Autodesk Fusion 360 part; units mm, degrees
(part 2 of 3)
  line L572 (36.370346, 133.075897) -> (50.340346, 133.075897)
  line L573 (36.370346, 142.565337) -> (36.370346, 137.556457)
  line L574 (50.340346, 118.508997) -> (50.340346, 123.517877)
  line L575 (35.557546, 127.017997) -> (35.557546, 123.517877)
  line L576 (151.165646, 135.961337) -> (151.165646, 139.461457)
  line L577 (36.370346, 95.958877) -> (36.370346, 94.978437)
  line L578 (35.557546, 76.908877) -> (36.370346, 76.908877)
  line L579 (50.340346, 75.928437) -> (50.340346, 76.908877)
  line L580 (40.807846, 170.435327) -> (40.807846, 172.435327)
  line L581 (50.340346, 114.028437) -> (50.340346, 115.008877)
  line L582 (75, 170.435327) -> (75, 160.233267)
  line L583 (50.340346, 137.556457) -> (50.340346, 142.565337)
  line L584 (151.165646, 139.461457) -> (150.352846, 139.461457)
  line L585 (51.153146, 123.517877) -> (51.153146, 127.017997)
  line L586 (51.153146, 118.508997) -> (50.340346, 118.508997)
  line L587 (36.370346, 123.517877) -> (36.370346, 118.508997)
  line L588 (50.340346, 89.898437) -> (36.370346, 89.898437)
  line L589 (50.340346, 85.417877) -> (51.153146, 85.417877)
  line L590 (35.557546, 95.958877) -> (36.370346, 95.958877)
  line L591 (35.557546, 134.056337) -> (36.370346, 134.056337)
  line L592 (165.973846, 183.698097) -> (174.0868, 183.698)
  line L593 (50.340346, 95.958877) -> (51.153146, 95.958877)
  line L594 (50.340346, 123.517877) -> (51.153146, 123.517877)
  line L595 (153.609126, 68.945977) -> (152.212126, 65.953857)
  line L596 (172.062226, 33.995577) -> (159.400326, 39.898537)
  line L597 (51.153146, 107.967997) -> (50.340346, 107.967997)
  line L598 (35.557546, 104.467877) -> (36.370346, 104.467877)
  line L599 (40.807846, 172.435327) -> (52.807846, 172.435327)
  line L600 (38.307846, 160.233267) -> (38.307846, 170.435327)
  circle A0 centre (216.558535, 69.898485) radius 1.5
  line L601 (36.370346, 80.408997) -> (35.557546, 80.408997)
  circle A1 centre (174.816574, 177.434124) radius 1.5
  line L602 (155.037046, 163.5842) -> (142.266246, 163.5842)
  arc A2 (221.924959, 66.584374) -> (218.538915, 75.886932) centre (215.580795, 69.542681) ccw
  line L603 (35.557546, 80.408997) -> (35.557546, 76.908877)
  line L604 (36.370346, 75.928437) -> (50.340346, 75.928437)
  line L605 (169.491746, 61.539337) -> (168.094746, 58.547217)
  line L606 (168.094746, 58.547217) -> (180.756646, 52.641717)
  circle A3 centre (106.66988, 49.713) radius 1.5
  line L607 (50.340346, 80.408997) -> (50.340346, 85.417877)
  line L608 (156.179606, 41.402217) -> (143.517706, 47.307717)
  line L609 (159.400326, 39.898537) -> (158.005866, 36.906417)
  arc A4 (181.0868, 97.809303) -> (185.12868, 91.465051) centre (188.0868, 97.809303) ccw
  line L610 (35.557546, 85.417877) -> (36.370346, 85.417877)
  circle A5 centre (26.263877, 177.434124) radius 1.5
  line L611 (50.340346, 107.967997) -> (50.340346, 108.948437)
  arc A6 (181.0868, 176.698) -> (174.0868, 183.698) centre (174.0868, 176.698) ccw
  line L612 (158.005866, 36.906417) -> (170.665226, 31.003457)
  line L613 (50.340346, 76.908877) -> (51.153146, 76.908877)
  line L614 (27, 183.698) -> (130.871308, 183.698)
  line L615 (51.153146, 88.917997) -> (50.340346, 88.917997)
  line L616 (51.153146, 76.908877) -> (51.153146, 80.408997)
  line L617 (166.268486, 63.043017) -> (153.609126, 68.945977)
  line L618 (50.340346, 88.917997) -> (50.340346, 89.898437)
  line L619 (152.212126, 65.953857) -> (164.874026, 60.050897)
  circle A7 centre (121.333346, 179.253097) radius 1.5
  line L620 (144.750746, 178.585077) -> (130.871308, 183.698)
  line L621 (181.0868, 176.698) -> (181.0868, 97.809303)
  line L622 (185.12868, 91.465051) -> (218.538915, 75.886932)
  line L623 (142.123246, 44.315597) -> (154.782606, 38.410097)
  line L624 (143.517706, 47.307717) -> (142.123246, 44.315597)
  line L625 (35.557546, 88.917997) -> (35.557546, 85.417877)
  line L626 (221.924959, 66.584374) -> (178.566521, -26.398891)
  line L627 (36.370346, 88.917997) -> (35.557546, 88.917997)
  line L628 (165.973846, 183.698097) -> (152.094146, 178.585077)
  circle A8 centre (26.263876, 53.119376) radius 1.5
  arc A9 (27, 183.698) -> (20, 176.698) centre (27, 176.698) ccw
  line L629 (52.807846, 170.435327) -> (75, 170.435327)
  line L630 (51.153146, 104.467877) -> (51.153146, 107.967997)
  line L631 (180.756646, 52.641717) -> (182.151106, 55.633837)
  line L632 (51.153146, 80.408997) -> (50.340346, 80.408997)
  line L633 (182.151106, 55.633837) -> (169.491746, 61.539337)
  line L634 (170.665226, 31.003457) -> (172.062226, 33.995577)
  line L635 (50.340346, 104.467877) -> (51.153146, 104.467877)
  line L636 (36.370346, 89.898437) -> (36.370346, 88.917997)
  line L637 (164.874026, 60.050897) -> (166.268486, 63.043017)
  line L638 (36.370346, 76.908877) -> (36.370346, 75.928437)
  line L639 (36.370346, 85.417877) -> (36.370346, 80.408997)
  line L640 (51.153146, 85.417877) -> (51.153146, 88.917997)
  line L641 (52.807846, 170.435327) -> (52.807846, 172.435327)
  line L642 (154.782606, 38.410097) -> (156.179606, 41.402217)
  line L643 (20, -23.440584) -> (20, 176.698)
  line L644 (155.037046, 174.584297) -> (155.037046, 177.084297)
  line L645 (38.307846, 170.435327) -> (40.807846, 170.435327)
  line L646 (144.750746, 178.585077) -> (145.537046, 178.585077)
  arc A10 (172.222357, -30.440584) -> (178.566521, -26.398891) centre (172.222357, -23.440584) ccw
  line L647 (40.807846, 158.233267) -> (52.807846, 158.233267)
  line L648 (142.266246, 177.084297) -> (145.537046, 177.084297)
  line L649 (145.537046, 177.084297) -> (145.537046, 178.585077)
  line L650 (38.307846, 160.233267) -> (40.807846, 160.233267)
  line L651 (151.537046, 178.585077) -> (151.537046, 177.084297)
  line L652 (142.266246, 177.084297) -> (142.266246, 173.541483)
  line L653 (158.032597, 166.625184) -> (158.033388, 174.584297)
  line L654 (52.807846, 160.233267) -> (75, 160.233267)
  circle A11 centre (26.263876, -24.176684) radius 1.5
  line L655 (155.037046, 163.5842) -> (155.037046, 166.62711)
  arc A12 (20, -23.440584) -> (27, -30.440584) centre (27, -23.440584) ccw
  line L656 (155.037046, 174.584297) -> (158.033388, 174.584297)
  line L657 (142.266246, 165.584297) -> (139.270694, 165.58237)
  line L658 (151.537046, 177.084297) -> (155.037046, 177.084297)
  line L659 (155.037046, 166.62711) -> (158.032597, 166.625184)
  circle A13 centre (172.941014, -24.568646) radius 1.5
  line L660 (172.222357, -30.440584) -> (27, -30.440584)
  line L661 (139.270694, 165.58237) -> (139.269904, 173.541483)
  line L662 (40.807846, 158.233267) -> (40.807846, 160.233267)
  line L663 (142.266246, 165.584297) -> (142.266246, 163.5842)
  line L664 (151.537046, 178.585077) -> (152.094146, 178.585077)
  line L665 (142.266246, 173.541483) -> (139.269904, 173.541483)
  line L666 (52.807846, 158.233267) -> (52.807846, 160.233267)
  line L667 (116.520046, 73.042997) -> (116.520046, 69.542877)
  line L668 (156.883186, 44.716917) -> (162.788686, 57.378817)
  line L669 (132.115646, 69.542877) -> (132.115646, 73.042997)
  line L670 (113.065646, 66.131657) -> (112.252846, 66.131657)
  line L671 (112.252846, 71.140537) -> (113.065646, 71.140537)
  line L672 (131.302846, 69.542877) -> (132.115646, 69.542877)
  line L673 (112.252846, 61.651097) -> (112.252846, 62.631537)
  line L674 (60.182846, 61.358997) -> (59.370046, 61.358997)
  line L675 (132.115646, 61.033877) -> (132.115646, 64.533997)
  line L676 (132.115646, 64.533997) -> (131.302846, 64.533997)
  line L677 (132.115646, 73.042997) -> (131.302846, 73.042997)
  line L678 (117.332846, 64.533997) -> (116.520046, 64.533997)
  line L679 (59.370046, 61.358997) -> (59.370046, 57.858877)
  line L680 (98.282846, 62.631537) -> (98.282846, 61.651097)
  line L681 (162.788686, 57.378817) -> (161.899686, 57.792837)
  line L682 (97.470046, 62.631537) -> (98.282846, 62.631537)
  line L683 (131.302846, 64.533997) -> (131.302846, 69.542877)
  line L684 (117.332846, 61.033877) -> (117.332846, 60.053437)
  line L685 (131.302846, 73.042997) -> (131.302846, 74.023437)
  line L686 (97.470046, 71.140537) -> (98.282846, 71.140537)
  line L687 (98.282846, 61.651097) -> (112.252846, 61.651097)
  line L688 (113.065646, 71.140537) -> (113.065646, 74.640657)
  line L689 (161.899686, 57.792837) -> (162.242586, 58.529437)
  line L690 (74.152846, 56.878437) -> (74.152846, 57.858877)
  line L691 (98.282846, 75.621097) -> (98.282846, 74.640657)
  line L692 (112.252846, 66.131657) -> (112.252846, 71.140537)
  line L693 (117.332846, 60.053437) -> (131.302846, 60.053437)
  line L694 (74.152846, 66.367877) -> (74.965646, 66.367877)
  line L695 (74.965646, 69.867997) -> (74.152846, 69.867997)
  line L696 (112.252846, 62.631537) -> (113.065646, 62.631537)
  line L697 (94.015646, 121.683997) -> (93.202846, 121.683997)
  line L698 (159.070126, 60.010257) -> (158.727226, 59.273657)
  line L699 (135.570046, 135.961337) -> (136.382846, 135.961337)
  line L700 (116.520046, 61.033877) -> (117.332846, 61.033877)
  line L701 (74.965646, 66.367877) -> (74.965646, 69.867997)
  line L702 (151.358686, 63.604357) -> (151.015786, 62.867757)
  line L703 (136.382846, 139.461457) -> (135.570046, 139.461457)
  line L704 (162.374666, 42.156597) -> (162.031766, 41.419997)
  line L705 (74.152846, 57.858877) -> (74.965646, 57.858877)
  line L706 (93.202846, 117.203437) -> (93.202846, 118.183877)
  line L707 (94.015646, 130.192997) -> (93.202846, 130.192997)
  line L708 (144.221286, 50.622417) -> (145.110286, 50.208397)
  line L709 (173.258566, 37.081677) -> (174.147566, 36.665117)
  line L710 (60.182846, 56.878437) -> (74.152846, 56.878437)
  line L711 (93.202846, 130.192997) -> (93.202846, 131.173437)
  line L712 (165.204226, 39.939177) -> (165.547126, 40.675777)
  line L713 (147.939846, 47.990977) -> (148.282746, 48.727577)
  line L714 (162.242586, 58.529437) -> (159.070126, 60.010257)
  line L715 (165.547126, 40.675777) -> (170.086106, 38.559957)
  line L716 (79.232846, 131.173437) -> (79.232846, 130.192997)
  line L717 (150.126786, 63.284317) -> (144.221286, 50.622417)
  line L718 (154.531146, 62.126077) -> (151.358686, 63.604357)
  line L719 (74.152846, 61.358997) -> (74.152846, 66.367877)
  line L720 (116.520046, 69.542877) -> (117.332846, 69.542877)
  line L721 (60.182846, 66.367877) -> (60.182846, 61.358997)
  line L722 (158.727226, 59.273657) -> (154.188246, 61.389477)
  line L723 (174.147566, 36.665117) -> (180.053066, 49.327017)
  line L724 (59.370046, 66.367877) -> (60.182846, 66.367877)
  line L725 (131.302846, 74.023437) -> (117.332846, 74.023437)
  line L726 (112.252846, 75.621097) -> (98.282846, 75.621097)
  line L727 (154.188246, 61.389477) -> (154.531146, 62.126077)
  line L728 (168.623066, 55.552557) -> (168.280166, 54.815957)
  line L729 (170.086106, 38.559957) -> (169.743206, 37.823357)
  line L730 (136.382846, 147.970457) -> (135.570046, 147.970457)
  line L731 (136.382846, 135.961337) -> (136.382846, 134.980897)
  line L732 (150.352846, 134.980897) -> (150.352846, 135.961337)
  line L733 (98.282846, 74.640657) -> (97.470046, 74.640657)
  line L734 (93.202846, 131.173437) -> (79.232846, 131.173437)
  line L735 (78.420046, 126.692877) -> (79.232846, 126.692877)
  line L736 (97.470046, 66.131657) -> (97.470046, 62.631537)
  line L737 (94.015646, 126.692877) -> (94.015646, 130.192997)
  line L738 (144.767386, 49.471797) -> (147.939846, 47.990977)
  line L739 (113.065646, 62.631537) -> (113.065646, 66.131657)
  line L740 (78.420046, 121.683997) -> (78.420046, 118.183877)
  line L741 (117.332846, 74.023437) -> (117.332846, 73.042997)
  line L742 (79.232846, 121.683997) -> (78.420046, 121.683997)
  line L743 (152.821726, 46.611757) -> (152.478826, 45.875157)
  line L744 (136.382846, 134.980897) -> (150.352846, 134.980897)
  line L745 (145.110286, 50.208397) -> (144.767386, 49.471797)
  line L746 (169.743206, 37.823357) -> (172.915666, 36.345077)
  line L747 (60.182846, 57.858877) -> (60.182846, 56.878437)
  line L748 (171.795526, 54.074277) -> (168.623066, 55.552557)
  line L749 (179.506966, 50.477637) -> (176.334506, 51.958457)
  line L750 (93.202846, 126.692877) -> (94.015646, 126.692877)
  line L751 (162.031766, 41.419997) -> (165.204226, 39.939177)
  line L752 (78.420046, 130.192997) -> (78.420046, 126.692877)
  line L753 (79.232846, 130.192997) -> (78.420046, 130.192997)
  line L754 (79.232846, 126.692877) -> (79.232846, 121.683997)
  line L755 (167.391166, 55.232517) -> (161.485666, 42.570617)
  line L756 (179.164066, 49.741037) -> (179.506966, 50.477637)
  line L757 (150.352846, 148.950897) -> (136.382846, 148.950897)
  line L758 (60.182846, 99.458997) -> (59.370046, 99.458997)
  line L759 (131.302846, 131.173437) -> (117.332846, 131.173437)
  line L760 (97.470046, 131.790657) -> (97.470046, 128.290537)
  line L761 (117.332846, 126.692877) -> (117.332846, 121.683997)
  line L762 (74.965646, 118.508997) -> (74.152846, 118.508997)
  line L763 (132.115646, 118.183877) -> (132.115646, 121.683997)
  line L764 (60.182846, 107.967997) -> (59.370046, 107.967997)
  line L765 (98.282846, 123.281657) -> (97.470046, 123.281657)
  line L766 (60.182846, 94.978437) -> (74.152846, 94.978437)
  line L767 (74.152846, 94.978437) -> (74.152846, 95.958877)
  line L768 (59.370046, 99.458997) -> (59.370046, 95.958877)
  line L769 (116.520046, 130.192997) -> (116.520046, 126.692877)
  line L770 (117.332846, 117.203437) -> (131.302846, 117.203437)
  line L771 (116.520046, 118.183877) -> (117.332846, 118.183877)
  line L772 (60.182846, 104.467877) -> (60.182846, 99.458997)
  line L773 (112.252846, 123.281657) -> (112.252846, 128.290537)
  line L774 (131.302846, 121.683997) -> (131.302846, 126.692877)
  line L775 (117.332846, 121.683997) -> (116.520046, 121.683997)
  line L776 (132.115646, 126.692877) -> (132.115646, 130.192997)
  line L777 (97.470046, 119.781537) -> (98.282846, 119.781537)
  line L778 (112.252846, 131.790657) -> (112.252846, 132.771097)
  line L779 (97.470046, 123.281657) -> (97.470046, 119.781537)
  line L780 (74.152846, 115.008877) -> (74.965646, 115.008877)
  line L781 (60.182846, 114.028437) -> (74.152846, 114.028437)
  line L782 (116.520046, 121.683997) -> (116.520046, 118.183877)
  line L783 (113.065646, 119.781537) -> (113.065646, 123.281657)
  line L784 (74.152846, 114.028437) -> (74.152846, 115.008877)
  line L785 (60.182846, 95.958877) -> (60.182846, 94.978437)
  line L786 (112.252846, 118.801097) -> (112.252846, 119.781537)
  line L787 (74.965646, 115.008877) -> (74.965646, 118.508997)
  line L788 (112.252846, 119.781537) -> (113.065646, 119.781537)
  line L789 (113.065646, 131.790657) -> (112.252846, 131.790657)
  line L790 (97.470046, 128.290537) -> (98.282846, 128.290537)
  line L791 (117.332846, 130.192997) -> (116.520046, 130.192997)
  line L792 (116.520046, 126.692877) -> (117.332846, 126.692877)
  line L793 (131.302846, 117.203437) -> (131.302846, 118.183877)
  line L794 (131.302846, 79.103437) -> (131.302846, 80.083877)
  line L795 (131.302846, 93.073437) -> (117.332846, 93.073437)
  line L796 (136.382846, 91.803437) -> (136.382846, 90.822997)
  line L797 (150.352846, 82.313997) -> (150.352846, 87.322877)
  line L798 (131.302846, 83.583997) -> (131.302846, 88.592877)
  line L799 (136.382846, 77.833437) -> (150.352846, 77.833437)
  line L800 (150.352846, 90.822997) -> (150.352846, 91.803437)
  line L801 (117.332846, 88.592877) -> (117.332846, 83.583997)
  line L802 (150.352846, 91.803437) -> (136.382846, 91.803437)
  line L803 (132.115646, 88.592877) -> (132.115646, 92.092997)
  line L804 (136.382846, 82.313997) -> (135.570046, 82.313997)
  line L805 (60.182846, 69.867997) -> (59.370046, 69.867997)
  line L806 (60.182846, 70.848437) -> (60.182846, 69.867997)
  line L807 (151.165646, 82.313997) -> (150.352846, 82.313997)
  line L808 (150.352846, 77.833437) -> (150.352846, 78.813877)
  line L809 (113.065646, 90.190537) -> (113.065646, 93.690657)
  line L810 (117.332846, 83.583997) -> (116.520046, 83.583997)
  line L811 (116.520046, 80.083877) -> (117.332846, 80.083877)
  line L812 (97.470046, 81.681537) -> (98.282846, 81.681537)
  line L813 (116.520046, 88.592877) -> (117.332846, 88.592877)
  line L814 (151.537046, 178.585077) -> (145.537046, 178.585077)
  line L815 (145.537046, 177.084297) -> (151.537046, 177.084297)
  constraint perpendicular L649 L814
  constraint perpendicular L651 L815
sketch "ErgoDOX Wrist Rest Case Layer 5 Bottom - Right" plane through (250, 0, 0) normal (0, 0, 1) x (1, 0, 0)
  line L0 (12.882842, 69.500174) -> (56.24128, -23.483091)
  line L1 (62.585444, -27.524784) -> (207.8078, -27.524784)
  line L2 (49.67912, 94.380851) -> (16.268885, 78.802732)
  line L3 (214.8078, -20.524784) -> (214.8078, 179.6138)
  line L4 (38.8078, 18.9158) -> (38.8078, 18.9158)
  arc A0 (207.8078, -27.524784) -> (214.8078, -20.524784) centre (207.8078, -20.524784) ccw
  arc A1 (60.721, 186.6138) -> (53.721, 179.6138) centre (60.721, 179.6138) ccw
  arc A2 (49.67912, 94.380851) -> (53.721, 100.725102) centre (46.721, 100.725102) ccw
  arc A3 (16.268885, 78.802732) -> (12.882842, 69.500174) centre (19.227006, 72.458481) ccw
  line L5 (53.721, 179.6138) -> (53.721, 100.725102)
  arc A4 (56.24128, -23.483091) -> (62.585444, -27.524784) centre (62.585444, -20.524784) ccw
  arc A5 (214.8078, 179.6138) -> (207.8078, 186.6138) centre (207.8078, 179.6138) ccw
  line L6 (207.8078, 186.6138) -> (60.721, 186.6138)
sketch "ErgoDOX Wrist Rest Case Layer 4 Spacer - Right" plane through (250, 0, 0) normal (0, 0, 1) x (1, 0, 0)
  line L0 (38.8078, 18.9158) -> (38.8078, 18.9158)
  line L1 (142.993195, 181.500877) -> (152.298355, 186.613897)
  line L2 (123.012155, 186.613897) -> (132.317315, 181.500877)
  circle A0 centre (208.543924, -21.260884) radius 1.25
  circle A1 centre (208.543924, 56.035176) radius 1.25
  line L3 (49.67912, 94.380851) -> (16.268885, 78.802732)
  circle A2 centre (61.866787, -21.652846) radius 1.25
  line L4 (214.8078, -20.524784) -> (214.8078, 179.6138)
  circle A3 centre (128.13792, 52.6288) radius 1.25
  circle A4 centre (208.543924, 180.349924) radius 1.25
  line L5 (103.9368, 186.6138) -> (123.012155, 186.613897)
  line L6 (132.291915, 181.500877) -> (142.993195, 181.500877)
  arc A5 (56.24128, -23.483091) -> (62.585444, -27.524784) centre (62.585444, -20.524784) ccw
  line L7 (12.882842, 69.500174) -> (56.24128, -23.483091)
  line L8 (207.8078, 186.6138) -> (152.298179, 186.6138)
  line L9 (62.585444, -27.524784) -> (207.8078, -27.524784)
  arc A6 (16.268885, 78.802732) -> (12.882842, 69.500174) centre (19.227006, 72.458481) ccw
  circle A7 centre (18.249265, 72.814285) radius 1.25
  line L10 (90.0571, 181.50078) -> (103.9368, 186.6138)
  line L11 (82.7137, 181.50078) -> (90.0571, 181.50078)
  line L12 (68.834, 186.6138) -> (82.7137, 181.50078)
  circle A8 centre (59.991226, 180.349924) radius 1.25
  circle A9 centre (113.4745, 182.1688) radius 1.25
  arc A10 (214.8078, 179.6138) -> (207.8078, 186.6138) centre (207.8078, 179.6138) ccw
  line L13 (68.834, 186.6138) -> (60.721, 186.6138)
  line L14 (53.721, 179.6138) -> (53.721, 100.725102)
  arc A11 (60.721, 186.6138) -> (53.721, 179.6138) centre (60.721, 179.6138) ccw
  arc A12 (207.8078, -27.524784) -> (214.8078, -20.524784) centre (207.8078, -20.524784) ccw
  arc A13 (49.67912, 94.380851) -> (53.721, 100.725102) centre (46.721, 100.725102) ccw
  line L15 (57.487107, 89.3158) -> (23.819783, 73.616614)
  line L16 (23.819783, 73.616614) -> (21.999561, 68.619276)
  line L17 (21.999561, 68.619276) -> (44.033775, 21.365862)
  line L18 (44.033775, 21.365862) -> (49.031231, 19.548605)
  line L19 (49.031231, 19.548605) -> (127.374058, 56.0738)
  line L20 (127.374058, 56.0738) -> (196.807014, 56.0738)
  line L21 (196.807014, 56.0738) -> (206.9178, 66.184586)
  line L22 (206.9178, 66.184586) -> (206.9178, 174.963014)
  line L23 (206.9178, 174.963014) -> (203.157014, 178.7238)
  line L24 (203.157014, 178.7238) -> (144.4084, 178.7238)
  line L25 (144.4084, 178.7238) -> (144.4084, 180.5018)
  line L26 (144.4084, 180.5018) -> (130.9022, 180.5018)
  line L27 (130.9022, 180.5018) -> (130.9022, 178.7238)
  line L28 (130.9022, 178.7238) -> (96.0468, 178.7238)
  line L29 (96.0468, 178.7238) -> (96.0468, 180.5018)
  line L30 (96.0468, 180.5018) -> (76.8764, 180.5018)
  line L31 (76.8764, 180.5018) -> (76.8764, 178.7238)
  line L32 (76.8764, 178.7238) -> (65.399518, 178.7238)
  line L33 (65.399518, 178.7238) -> (61.611, 174.965349)
  line L34 (61.611, 174.965349) -> (61.611, 89.3158)
  line L35 (61.611, 89.3158) -> (57.487107, 89.3158)
  dimension "d36" = 2.5
  constraint equal A8 A9
  constraint equal A4 A8
  constraint equal A7 A8
  constraint equal A3 A8
  constraint equal A1 A8
  constraint equal A2 A8
  constraint equal A0 A8
  measures "d36" diameter of A8
sketch "ErgoDOX Wrist Rest Case Layer 3 Plate - Right" plane through (250, 0, 85) normal (0, 0, 1) x (1, 0, 0)
  line L0 (80.1878, 138.87704) -> (79.375, 138.87704)
  line L1 (65.405, 142.37716) -> (65.405, 147.38604)
  line L2 (79.375, 128.05664) -> (79.375, 114.08664)
  line L3 (74.89444, 114.08664) -> (69.88556, 114.08664)
  line L4 (80.1878, 150.88616) -> (80.1878, 147.38604)
  line L5 (78.39456, 128.05664) -> (79.375, 128.05664)
  line L6 (64.5922, 142.37716) -> (65.405, 142.37716)
  line L7 (66.38544, 99.48164) -> (66.38544, 100.29444)
  line L8 (78.39456, 99.48164) -> (79.375, 99.48164)
  line L9 (79.375, 142.37716) -> (80.1878, 142.37716)
  line L10 (64.5922, 147.38604) -> (64.5922, 150.88616)
  line L11 (74.89444, 128.05664) -> (74.89444, 128.86944)
  line L12 (80.1878, 147.38604) -> (79.375, 147.38604)
  line L13 (64.5922, 138.87704) -> (64.5922, 142.37716)
  line L14 (66.38544, 100.29444) -> (69.88556, 100.29444)
  line L15 (66.38544, 128.86944) -> (69.88556, 128.86944)
  line L16 (83.5, 180) -> (83.5, 181.50078)
  line L17 (65.405, 99.48164) -> (66.38544, 99.48164)
  line L18 (74.89444, 99.48164) -> (74.89444, 100.29444)
  line L19 (65.405, 137.8966) -> (65.405, 138.87704)
  line L20 (69.88556, 114.08664) -> (69.88556, 113.27384)
  line L21 (79.375, 137.8966) -> (65.405, 137.8966)
  line L22 (69.88556, 113.27384) -> (66.38544, 113.27384)
  line L23 (65.405, 147.38604) -> (64.5922, 147.38604)
  line L24 (79.375, 151.8666) -> (79.375, 150.88616)
  line L25 (78.39456, 128.86944) -> (78.39456, 128.05664)
  line L26 (78.39456, 113.27384) -> (74.89444, 113.27384)
  line L27 (69.88556, 99.48164) -> (74.89444, 99.48164)
  line L28 (65.405, 138.87704) -> (64.5922, 138.87704)
  line L29 (65.405, 85.51164) -> (65.405, 99.48164)
  line L30 (79.375, 147.38604) -> (79.375, 142.37716)
  line L31 (66.38544, 128.05664) -> (66.38544, 128.86944)
  line L32 (79.375, 150.88616) -> (80.1878, 150.88616)
  line L33 (74.89444, 128.86944) -> (78.39456, 128.86944)
  line L34 (64.5922, 150.88616) -> (65.405, 150.88616)
  line L35 (79.375, 114.08664) -> (78.39456, 114.08664)
  line L36 (78.39456, 114.08664) -> (78.39456, 113.27384)
  line L37 (159.8422, 102.3747) -> (160.655, 102.3747)
  line L38 (174.625, 102.3747) -> (175.4378, 102.3747)
  line L39 (122.555, 126.19736) -> (122.555, 131.20624)
  line L40 (122.555, 134.70636) -> (122.555, 135.6868)
  line L41 (159.8422, 107.38358) -> (159.8422, 110.8837)
  line L42 (122.555, 131.20624) -> (121.7422, 131.20624)
  line L43 (136.525, 122.69724) -> (136.525, 121.7168)
  line L44 (137.3378, 122.69724) -> (136.525, 122.69724)
  line L45 (174.625, 111.86414) -> (174.625, 110.8837)
  line L46 (103.505, 134.08914) -> (117.475, 134.08914)
  line L47 (103.505, 121.09958) -> (102.6922, 121.09958)
  line L48 (160.655, 110.8837) -> (160.655, 111.86414)
  line L49 (102.6922, 124.5997) -> (103.505, 124.5997)
  line L50 (122.555, 121.7168) -> (122.555, 122.69724)
  line L51 (102.6922, 129.60858) -> (102.6922, 133.1087)
  line L52 (121.7422, 122.69724) -> (121.7422, 126.19736)
  line L53 (160.655, 97.89414) -> (160.655, 98.87458)
  line L54 (117.475, 133.1087) -> (118.2878, 133.1087)
  line L55 (117.475, 120.11914) -> (103.505, 120.11914)
  line L56 (155.575, 115.03914) -> (155.575, 114.0587)
  line L57 (175.4378, 110.8837) -> (175.4378, 107.38358)
  line L58 (103.505, 124.5997) -> (103.505, 129.60858)
  line L59 (160.655, 98.87458) -> (159.8422, 98.87458)
  line L60 (117.475, 124.5997) -> (118.2878, 124.5997)
  line L61 (103.505, 129.60858) -> (102.6922, 129.60858)
  line L62 (141.605, 115.03914) -> (155.575, 115.03914)
  line L63 (174.625, 107.38358) -> (174.625, 102.3747)
  line L64 (175.4378, 102.3747) -> (175.4378, 98.87458)
  line L65 (103.505, 120.11914) -> (103.505, 121.09958)
  line L66 (160.655, 111.86414) -> (174.625, 111.86414)
  line L67 (160.655, 107.38358) -> (159.8422, 107.38358)
  line L68 (98.425, 112.7887) -> (99.2378, 112.7887)
  line L69 (136.525, 112.15624) -> (136.525, 107.14736)
  line L70 (122.555, 115.65636) -> (122.555, 116.6368)
  line L71 (117.475, 101.06914) -> (103.505, 101.06914)
  line L72 (121.7422, 103.64724) -> (121.7422, 107.14736)
  line L73 (122.555, 107.14736) -> (122.555, 112.15624)
  line L74 (103.505, 115.03914) -> (117.475, 115.03914)
  line L75 (141.605, 105.5497) -> (141.605, 110.55858)
  line L76 (136.525, 107.14736) -> (137.3378, 107.14736)
  line L77 (141.605, 101.06914) -> (141.605, 102.04958)
  line L78 (140.7922, 110.55858) -> (140.7922, 114.0587)
  line L79 (141.605, 114.0587) -> (141.605, 115.03914)
  line L80 (136.525, 102.6668) -> (122.555, 102.6668)
  line L81 (122.555, 102.6668) -> (122.555, 103.64724)
  line L82 (137.3378, 103.64724) -> (136.525, 103.64724)
  line L83 (122.555, 112.15624) -> (121.7422, 112.15624)
  line L84 (118.2878, 110.55858) -> (117.475, 110.55858)
  line L85 (137.3378, 112.15624) -> (136.525, 112.15624)
  line L86 (103.505, 110.55858) -> (102.6922, 110.55858)
  line L87 (84.455, 113.76914) -> (98.425, 113.76914)
  line L88 (136.525, 103.64724) -> (136.525, 102.6668)
  line L89 (140.7922, 102.04958) -> (140.7922, 105.5497)
  line L90 (103.505, 101.06914) -> (103.505, 102.04958)
  line L91 (102.6922, 110.55858) -> (102.6922, 114.0587)
  line L92 (155.575, 101.06914) -> (141.605, 101.06914)
  line L93 (102.6922, 105.5497) -> (103.505, 105.5497)
  line L94 (137.3378, 115.65636) -> (137.3378, 112.15624)
  line L95 (98.425, 113.76914) -> (98.425, 112.7887)
  line L96 (140.7922, 105.5497) -> (141.605, 105.5497)
  line L97 (118.2878, 105.5497) -> (118.2878, 102.04958)
  line L98 (121.7422, 107.14736) -> (122.555, 107.14736)
  line L99 (122.555, 103.64724) -> (121.7422, 103.64724)
  line L100 (99.2378, 112.7887) -> (99.2378, 109.28858)
  line L101 (98.425, 109.28858) -> (98.425, 104.2797)
  line L102 (121.7422, 115.65636) -> (122.555, 115.65636)
  line L103 (121.7422, 112.15624) -> (121.7422, 115.65636)
  line L104 (117.475, 105.5497) -> (118.2878, 105.5497)
  line L105 (118.2878, 102.04958) -> (117.475, 102.04958)
  line L106 (117.475, 102.04958) -> (117.475, 101.06914)
  line L107 (122.555, 116.6368) -> (136.525, 116.6368)
  line L108 (103.505, 114.0587) -> (103.505, 115.03914)
  line L109 (99.2378, 109.28858) -> (98.425, 109.28858)
  line L110 (118.2878, 114.0587) -> (118.2878, 110.55858)
  line L111 (103.505, 105.5497) -> (103.505, 110.55858)
  line L112 (98.425, 104.2797) -> (99.2378, 104.2797)
  line L113 (117.475, 114.0587) -> (118.2878, 114.0587)
  line L114 (141.605, 102.04958) -> (140.7922, 102.04958)
  line L115 (103.505, 102.04958) -> (102.6922, 102.04958)
  line L116 (137.3378, 107.14736) -> (137.3378, 103.64724)
  line L117 (141.605, 110.55858) -> (140.7922, 110.55858)
  line L118 (102.6922, 102.04958) -> (102.6922, 105.5497)
  line L119 (102.6922, 114.0587) -> (103.505, 114.0587)
  line L120 (99.2378, 104.2797) -> (99.2378, 100.77958)
  line L121 (117.475, 110.55858) -> (117.475, 105.5497)
  line L122 (140.7922, 114.0587) -> (141.605, 114.0587)
  line L123 (136.525, 115.65636) -> (137.3378, 115.65636)
  line L124 (99.2378, 100.77958) -> (98.425, 100.77958)
  line L125 (117.475, 115.03914) -> (117.475, 114.0587)
  line L126 (136.525, 116.6368) -> (136.525, 115.65636)
  line L127 (98.425, 100.77958) -> (98.425, 99.79914)
  line L128 (84.455, 99.79914) -> (84.455, 100.77958)
  line L129 (84.455, 100.77958) -> (83.6422, 100.77958)
  line L130 (83.6422, 100.77958) -> (83.6422, 104.2797)
  line L131 (98.425, 99.79914) -> (84.455, 99.79914)
  line L132 (160.655, 91.8337) -> (160.655, 92.81414)
  line L133 (84.455, 104.2797) -> (84.455, 109.28858)
  line L134 (84.455, 112.7887) -> (84.455, 113.76914)
  line L135 (159.8422, 91.8337) -> (160.655, 91.8337)
  line L136 (174.625, 83.3247) -> (175.4378, 83.3247)
  line L137 (156.3878, 91.50858) -> (155.575, 91.50858)
  line L138 (83.6422, 104.2797) -> (84.455, 104.2797)
  line L139 (174.625, 92.81414) -> (174.625, 91.8337)
  line L140 (174.625, 91.8337) -> (175.4378, 91.8337)
  line L141 (174.625, 88.33358) -> (174.625, 83.3247)
  line L142 (137.3378, 96.60636) -> (137.3378, 93.10624)
  line L143 (155.575, 95.0087) -> (156.3878, 95.0087)
  line L144 (156.3878, 82.99958) -> (155.575, 82.99958)
  line L145 (160.655, 83.3247) -> (160.655, 88.33358)
  line L146 (140.7922, 91.50858) -> (140.7922, 95.0087)
  line L147 (137.3378, 84.59724) -> (136.525, 84.59724)
  line L148 (136.525, 83.6168) -> (122.555, 83.6168)
  line L149 (121.7422, 88.09736) -> (122.555, 88.09736)
  line L150 (122.555, 97.5868) -> (136.525, 97.5868)
  line L151 (137.3378, 88.09736) -> (137.3378, 84.59724)
  line L152 (175.4378, 79.82458) -> (174.625, 79.82458)
  line L153 (159.8422, 88.33358) -> (159.8422, 91.8337)
  line L154 (174.625, 79.82458) -> (174.625, 78.84414)
  line L155 (140.7922, 95.0087) -> (141.605, 95.0087)
  line L156 (136.525, 97.5868) -> (136.525, 96.60636)
  line L157 (159.8422, 79.82458) -> (159.8422, 83.3247)
  line L158 (141.605, 86.4997) -> (141.605, 91.50858)
  line L159 (122.555, 88.09736) -> (122.555, 93.10624)
  line L160 (121.7422, 84.59724) -> (121.7422, 88.09736)
  line L161 (136.525, 88.09736) -> (137.3378, 88.09736)
  line L162 (155.575, 86.4997) -> (156.3878, 86.4997)
  line L163 (155.575, 91.50858) -> (155.575, 86.4997)
  line L164 (155.575, 95.98914) -> (155.575, 95.0087)
  line L165 (160.655, 88.33358) -> (159.8422, 88.33358)
  line L166 (140.7922, 82.99958) -> (140.7922, 86.4997)
  line L167 (140.7922, 86.4997) -> (141.605, 86.4997)
  line L168 (122.555, 84.59724) -> (121.7422, 84.59724)
  line L169 (175.4378, 88.33358) -> (174.625, 88.33358)
  line L170 (141.605, 95.98914) -> (155.575, 95.98914)
  line L171 (83.6422, 109.28858) -> (83.6422, 112.7887)
  line L172 (141.605, 91.50858) -> (140.7922, 91.50858)
  line L173 (136.525, 84.59724) -> (136.525, 83.6168)
  line L174 (141.605, 82.99958) -> (140.7922, 82.99958)
  line L175 (160.655, 79.82458) -> (159.8422, 79.82458)
  line L176 (83.6422, 112.7887) -> (84.455, 112.7887)
  line L177 (155.575, 82.99958) -> (155.575, 82.01914)
  line L178 (175.4378, 91.8337) -> (175.4378, 88.33358)
  line L179 (174.625, 78.84414) -> (160.655, 78.84414)
  line L180 (160.655, 78.84414) -> (160.655, 79.82458)
  line L181 (156.3878, 95.0087) -> (156.3878, 91.50858)
  line L182 (136.525, 93.10624) -> (136.525, 88.09736)
  line L183 (84.455, 109.28858) -> (83.6422, 109.28858)
  line L184 (136.525, 96.60636) -> (137.3378, 96.60636)
  line L185 (156.3878, 86.4997) -> (156.3878, 82.99958)
  line L186 (160.655, 92.81414) -> (174.625, 92.81414)
  line L187 (155.575, 82.01914) -> (141.605, 82.01914)
  line L188 (141.605, 82.01914) -> (141.605, 82.99958)
  line L189 (137.3378, 93.10624) -> (136.525, 93.10624)
  line L190 (122.555, 83.6168) -> (122.555, 84.59724)
  line L191 (141.605, 95.0087) -> (141.605, 95.98914)
  line L192 (122.555, 93.10624) -> (121.7422, 93.10624)
  line L193 (159.8422, 83.3247) -> (160.655, 83.3247)
  line L194 (175.4378, 83.3247) -> (175.4378, 79.82458)
  line L195 (121.7422, 93.10624) -> (121.7422, 96.60636)
  line L196 (118.2878, 82.99958) -> (117.475, 82.99958)
  line L197 (103.505, 86.4997) -> (103.505, 91.50858)
  line L198 (103.505, 95.98914) -> (117.475, 95.98914)
  line L199 (118.2878, 95.0087) -> (118.2878, 91.50858)
  line L200 (99.2378, 85.2297) -> (99.2378, 81.72958)
  line L201 (175.4378, 72.7837) -> (175.4378, 69.28358)
  line L202 (117.475, 95.0087) -> (118.2878, 95.0087)
  line L203 (174.625, 69.28358) -> (174.625, 64.2747)
  line L204 (174.625, 64.2747) -> (175.4378, 64.2747)
  line L205 (174.625, 72.7837) -> (175.4378, 72.7837)
  line L206 (159.8422, 72.7837) -> (160.655, 72.7837)
  line L207 (84.455, 80.74914) -> (84.455, 81.72958)
  line L208 (122.555, 96.60636) -> (122.555, 97.5868)
  line L209 (160.655, 60.77458) -> (159.8422, 60.77458)
  line L210 (117.475, 82.99958) -> (117.475, 82.01914)
  line L211 (122.555, 78.5368) -> (136.525, 78.5368)
  line L212 (99.2378, 90.23858) -> (98.425, 90.23858)
  line L213 (98.425, 80.74914) -> (84.455, 80.74914)
  line L214 (83.6422, 81.72958) -> (83.6422, 85.2297)
  line L215 (117.475, 91.50858) -> (117.475, 86.4997)
  line L216 (83.6422, 90.23858) -> (83.6422, 93.7387)
  line L217 (102.6922, 95.0087) -> (103.505, 95.0087)
  line L218 (102.6922, 82.99958) -> (102.6922, 86.4997)
  line L219 (136.525, 78.5368) -> (136.525, 77.55636)
  line L220 (98.425, 85.2297) -> (99.2378, 85.2297)
  line L221 (160.655, 69.28358) -> (159.8422, 69.28358)
  line L222 (83.6422, 93.7387) -> (84.455, 93.7387)
  line L223 (117.475, 82.01914) -> (103.505, 82.01914)
  line L224 (99.2378, 81.72958) -> (98.425, 81.72958)
  line L225 (98.425, 81.72958) -> (98.425, 80.74914)
  line L226 (84.455, 85.2297) -> (84.455, 90.23858)
  line L227 (102.6922, 86.4997) -> (103.505, 86.4997)
  line L228 (103.505, 91.50858) -> (102.6922, 91.50858)
  line L229 (103.505, 95.0087) -> (103.505, 95.98914)
  line L230 (117.475, 86.4997) -> (118.2878, 86.4997)
  line L231 (103.505, 82.99958) -> (102.6922, 82.99958)
  line L232 (174.625, 73.76414) -> (174.625, 72.7837)
  line L233 (175.4378, 64.2747) -> (175.4378, 60.77458)
  line L234 (121.7422, 96.60636) -> (122.555, 96.60636)
  line L235 (98.425, 94.71914) -> (98.425, 93.7387)
  line L236 (118.2878, 91.50858) -> (117.475, 91.50858)
  line L237 (99.2378, 93.7387) -> (99.2378, 90.23858)
  line L238 (98.425, 93.7387) -> (99.2378, 93.7387)
  line L239 (175.4378, 60.77458) -> (174.625, 60.77458)
  line L240 (84.455, 90.23858) -> (83.6422, 90.23858)
  line L241 (103.505, 82.01914) -> (103.505, 82.99958)
  line L242 (83.6422, 85.2297) -> (84.455, 85.2297)
  line L243 (174.625, 60.77458) -> (174.625, 59.79414)
  line L244 (84.455, 81.72958) -> (83.6422, 81.72958)
  line L245 (84.455, 94.71914) -> (98.425, 94.71914)
  line L246 (98.425, 90.23858) -> (98.425, 85.2297)
  line L247 (84.455, 93.7387) -> (84.455, 94.71914)
  line L248 (118.2878, 86.4997) -> (118.2878, 82.99958)
  line L249 (160.655, 72.7837) -> (160.655, 73.76414)
  line L250 (160.655, 73.76414) -> (174.625, 73.76414)
  line L251 (159.8422, 60.77458) -> (159.8422, 64.2747)
  line L252 (160.655, 64.2747) -> (160.655, 69.28358)
  line L253 (102.6922, 91.50858) -> (102.6922, 95.0087)
  line L254 (82.32902, 48.79086) -> (79.15656, 47.31258)
  line L255 (175.4378, 69.28358) -> (174.625, 69.28358)
  line L256 (117.475, 63.94958) -> (117.475, 62.96914)
  line L257 (103.505, 63.94958) -> (102.6922, 63.94958)
  line L258 (72.56526, 61.44514) -> (75.73772, 62.92596)
  line L259 (136.525, 64.5668) -> (122.555, 64.5668)
  line L260 (160.655, 59.79414) -> (160.655, 60.77458)
  line L261 (159.8422, 64.2747) -> (160.655, 64.2747)
  line L262 (174.625, 59.79414) -> (160.655, 59.79414)
  line L263 (117.475, 95.98914) -> (117.475, 95.0087)
  line L264 (159.8422, 69.28358) -> (159.8422, 72.7837)
  line L265 (155.575, 110.55858) -> (155.575, 105.5497)
  line L266 (156.3878, 105.5497) -> (156.3878, 102.04958)
  line L267 (137.3378, 126.19736) -> (137.3378, 122.69724)
  line L268 (174.625, 98.87458) -> (174.625, 97.89414)
  line L269 (159.8422, 98.87458) -> (159.8422, 102.3747)
  line L270 (175.4378, 107.38358) -> (174.625, 107.38358)
  line L271 (155.575, 105.5497) -> (156.3878, 105.5497)
  line L272 (136.525, 121.7168) -> (122.555, 121.7168)
  line L273 (136.525, 126.19736) -> (137.3378, 126.19736)
  line L274 (118.2878, 121.09958) -> (117.475, 121.09958)
  line L275 (174.625, 97.89414) -> (160.655, 97.89414)
  line L276 (103.505, 133.1087) -> (103.505, 134.08914)
  line L277 (174.625, 110.8837) -> (175.4378, 110.8837)
  line L278 (155.575, 114.0587) -> (156.3878, 114.0587)
  line L279 (117.475, 134.08914) -> (117.475, 133.1087)
  line L280 (102.6922, 121.09958) -> (102.6922, 124.5997)
  line L281 (175.4378, 98.87458) -> (174.625, 98.87458)
  line L282 (156.3878, 102.04958) -> (155.575, 102.04958)
  line L283 (156.3878, 110.55858) -> (155.575, 110.55858)
  line L284 (155.575, 102.04958) -> (155.575, 101.06914)
  line L285 (121.7422, 126.19736) -> (122.555, 126.19736)
  line L286 (117.475, 129.60858) -> (117.475, 124.5997)
  line L287 (102.6922, 133.1087) -> (103.505, 133.1087)
  line L288 (66.7131, 61.46292) -> (54.0512, 55.55742)
  line L289 (183.6547, 83.3247) -> (184.4675, 83.3247)
  line L290 (133.79196, 177.5) -> (131, 177.5)
  line L291 (68.834, 186.6138) -> (60.721045, 186.613703)
  line L292 (132.29196, 181.50078) -> (133.79196, 181.50078)
  line L293 (183.6547, 91.8337) -> (184.4675, 91.8337)
  line L294 (69.93382, 62.9666) -> (68.53936, 65.95872)
  line L295 (76.80198, 39.82212) -> (64.14262, 33.91916)
  line L296 (92.7708, 166.5) -> (92.7708, 169.542814)
  line L297 (75.40752, 42.81424) -> (76.80198, 39.82212)
  line L298 (80, 168.5) -> (80, 166.5)
  line L299 (119, 172.847) -> (131, 172.847)
  line L300 (80, 180) -> (80, 176.457186)
  line L301 (207.807845, 186.613703) -> (152.2984, 186.6138)
  line L302 (89.5, 181.50078) -> (90.0571, 181.50078)
  line L303 (90.0571, 181.50078) -> (103.9368, 186.6138)
  line L304 (111.648837, 167.351435) -> (105.901125, 161.603724)
  line L305 (122.555, 69.04736) -> (122.555, 74.05624)
  line L306 (122.555, 64.5668) -> (122.555, 65.54724)
  line L307 (136.525, 77.55636) -> (137.3378, 77.55636)
  line L308 (72.01916, 60.29452) -> (72.90816, 60.70854)
  line L309 (121.7422, 69.04736) -> (122.555, 69.04736)
  line L310 (117.475, 76.93914) -> (117.475, 75.9587)
  line L311 (121.7422, 74.05624) -> (121.7422, 77.55636)
  line L312 (117.475, 62.96914) -> (103.505, 62.96914)
  line L313 (102.6922, 63.94958) -> (102.6922, 67.4497)
  line L314 (75.73772, 62.92596) -> (76.08062, 62.18936)
  line L315 (118.2878, 75.9587) -> (118.2878, 72.45858)
  line L316 (79.15656, 47.31258) -> (78.81366, 48.04918)
  line L317 (103.505, 67.4497) -> (103.505, 72.45858)
  line L318 (83.79206, 65.78346) -> (84.68106, 66.20002)
  line L319 (118.2878, 72.45858) -> (117.475, 72.45858)
  line L320 (90.58656, 53.53812) -> (89.69756, 53.1241)
  line L321 (102.6922, 72.45858) -> (102.6922, 75.9587)
  line L322 (118.2878, 63.94958) -> (117.475, 63.94958)
  line L323 (118.2878, 67.4497) -> (118.2878, 63.94958)
  line L324 (72.90816, 60.70854) -> (72.56526, 61.44514)
  line L325 (83.44916, 66.52006) -> (83.79206, 65.78346)
  line L326 (86.868, 50.90668) -> (86.5251, 51.64328)
  line L327 (137.3378, 69.04736) -> (137.3378, 65.54724)
  line L328 (80.6196, 64.30518) -> (80.2767, 65.04178)
  line L329 (122.555, 65.54724) -> (121.7422, 65.54724)
  line L330 (136.525, 65.54724) -> (136.525, 64.5668)
  line L331 (89.69756, 53.1241) -> (90.04046, 52.3875)
  line L332 (121.7422, 77.55636) -> (122.555, 77.55636)
  line L333 (86.5251, 51.64328) -> (81.98612, 49.52746)
  line L334 (90.04046, 52.3875) -> (86.868, 50.90668)
  line L335 (78.81366, 48.04918) -> (77.92466, 47.63262)
  line L336 (103.505, 75.9587) -> (103.505, 76.93914)
  line L337 (77.92466, 47.63262) -> (72.01916, 60.29452)
  line L338 (137.3378, 77.55636) -> (137.3378, 74.05624)
  line L339 (103.505, 72.45858) -> (102.6922, 72.45858)
  line L340 (54.75478, 52.24272) -> (55.64378, 52.65674)
  line L341 (55.64378, 52.65674) -> (55.30088, 53.39334)
  line L342 (55.30088, 53.39334) -> (58.47334, 54.87416)
  line L343 (58.47334, 54.87416) -> (58.81624, 54.13756)
  line L344 (84.68106, 66.20002) -> (90.58656, 53.53812)
  line L345 (58.81624, 54.13756) -> (63.35522, 56.25338)
  line L346 (136.525, 69.04736) -> (137.3378, 69.04736)
  line L347 (60.66028, 39.58082) -> (54.75478, 52.24272)
  line L348 (156.3878, 124.5997) -> (156.3878, 121.09958)
  line L349 (198.4375, 148.98116) -> (199.2503, 148.98116)
  line L350 (66.18478, 58.46826) -> (66.52768, 57.73166)
  line L351 (66.52768, 57.73166) -> (67.41668, 58.14822)
  line L352 (102.6922, 67.4497) -> (103.505, 67.4497)
  line L353 (84.455, 147.38604) -> (83.6422, 147.38604)
  line L354 (122.555, 77.55636) -> (122.555, 78.5368)
  line L355 (117.475, 67.4497) -> (118.2878, 67.4497)
  line L356 (122.555, 74.05624) -> (121.7422, 74.05624)
  line L357 (121.7422, 65.54724) -> (121.7422, 69.04736)
  line L358 (199.2503, 145.48104) -> (198.4375, 145.48104)
  line L359 (199.2503, 136.97204) -> (198.4375, 136.97204)
  line L360 (155.575, 134.08914) -> (155.575, 133.1087)
  line L361 (80.2767, 65.04178) -> (83.44916, 66.52006)
  line L362 (137.3378, 74.05624) -> (136.525, 74.05624)
  line L363 (81.98612, 49.52746) -> (82.32902, 48.79086)
  line L364 (103.505, 62.96914) -> (103.505, 63.94958)
  line L365 (103.505, 76.93914) -> (117.475, 76.93914)
  line L366 (136.525, 74.05624) -> (136.525, 69.04736)
  line L367 (137.3378, 65.54724) -> (136.525, 65.54724)
  line L368 (117.475, 72.45858) -> (117.475, 67.4497)
  line L369 (117.475, 75.9587) -> (118.2878, 75.9587)
  line L370 (102.6922, 75.9587) -> (103.505, 75.9587)
  line L371 (76.08062, 62.18936) -> (80.6196, 64.30518)
  line L372 (156.3878, 121.09958) -> (155.575, 121.09958)
  line L373 (141.605, 134.08914) -> (155.575, 134.08914)
  line L374 (98.425, 137.8966) -> (84.455, 137.8966)
  line L375 (141.605, 129.60858) -> (140.7922, 129.60858)
  line L376 (141.605, 133.1087) -> (141.605, 134.08914)
  line L377 (99.2378, 150.88616) -> (99.2378, 147.38604)
  line L378 (83.6422, 142.37716) -> (84.455, 142.37716)
  line L379 (61.89218, 39.26078) -> (61.54928, 39.99738)
  line L380 (198.4375, 145.48104) -> (198.4375, 140.47216)
  line L381 (199.2503, 148.98116) -> (199.2503, 145.48104)
  line L382 (98.425, 147.38604) -> (98.425, 142.37716)
  line L383 (155.575, 129.60858) -> (155.575, 124.5997)
  line L384 (199.2503, 140.47216) -> (199.2503, 136.97204)
  line L385 (72.43318, 45.0723) -> (72.77608, 44.3357)
  line L386 (84.455, 137.8966) -> (84.455, 138.87704)
  line L387 (140.7922, 133.1087) -> (141.605, 133.1087)
  line L388 (156.3878, 129.60858) -> (155.575, 129.60858)
  line L389 (98.425, 138.87704) -> (98.425, 137.8966)
  line L390 (69.60362, 42.85488) -> (69.26072, 43.59148)
  line L391 (198.4375, 140.47216) -> (199.2503, 140.47216)
  line L392 (198.4375, 136.97204) -> (198.4375, 135.9916)
  line L393 (61.54928, 39.99738) -> (60.66028, 39.58082)
  line L394 (156.3878, 133.1087) -> (156.3878, 129.60858)
  line L395 (64.72174, 41.47566) -> (65.06464, 40.73906)
  line L396 (155.575, 124.5997) -> (156.3878, 124.5997)
  line L397 (73.32218, 45.48632) -> (72.43318, 45.0723)
  line L398 (83.6422, 150.88616) -> (84.455, 150.88616)
  line L399 (99.2378, 147.38604) -> (98.425, 147.38604)
  line L400 (63.01232, 56.98998) -> (66.18478, 58.46826)
  line L401 (155.575, 133.1087) -> (156.3878, 133.1087)
  line L402 (140.7922, 124.5997) -> (141.605, 124.5997)
  line L403 (198.4375, 117.92458) -> (198.4375, 116.94414)
  line L404 (72.77608, 44.3357) -> (69.60362, 42.85488)
  line L405 (98.425, 150.88616) -> (99.2378, 150.88616)
  line L406 (198.4375, 111.86414) -> (198.4375, 110.8837)
  line L407 (198.4375, 91.8337) -> (199.2503, 91.8337)
  line L408 (199.2503, 126.43358) -> (198.4375, 126.43358)
  line L409 (199.2503, 91.8337) -> (199.2503, 88.33358)
  line L410 (183.6547, 121.4247) -> (184.4675, 121.4247)
  line L411 (184.4675, 110.8837) -> (184.4675, 111.86414)
  line L412 (198.4375, 83.3247) -> (199.2503, 83.3247)
  line L413 (155.575, 120.11914) -> (141.605, 120.11914)
  line L414 (141.605, 120.11914) -> (141.605, 121.09958)
  line L415 (184.4675, 149.9616) -> (198.4375, 149.9616)
  line L416 (98.425, 142.37716) -> (99.2378, 142.37716)
  line L417 (84.455, 150.88616) -> (84.455, 151.8666)
  line L418 (84.455, 142.37716) -> (84.455, 147.38604)
  line L419 (140.7922, 129.60858) -> (140.7922, 133.1087)
  line L420 (84.455, 138.87704) -> (83.6422, 138.87704)
  line L421 (67.41668, 58.14822) -> (73.32218, 45.48632)
  line L422 (83.6422, 147.38604) -> (83.6422, 150.88616)
  line L423 (84.455, 151.8666) -> (98.425, 151.8666)
  line L424 (98.425, 151.8666) -> (98.425, 150.88616)
  line L425 (83.6422, 138.87704) -> (83.6422, 142.37716)
  line L426 (155.575, 121.09958) -> (155.575, 120.11914)
  line L427 (141.605, 121.09958) -> (140.7922, 121.09958)
  line L428 (140.7922, 121.09958) -> (140.7922, 124.5997)
  line L429 (99.2378, 142.37716) -> (99.2378, 138.87704)
  line L430 (198.4375, 149.9616) -> (198.4375, 148.98116)
  line L431 (199.2503, 102.3747) -> (199.2503, 98.87458)
  line L432 (63.35522, 56.25338) -> (63.01232, 56.98998)
  line L433 (184.4675, 107.38358) -> (183.6547, 107.38358)
  line L434 (69.26072, 43.59148) -> (64.72174, 41.47566)
  line L435 (184.4675, 92.81414) -> (198.4375, 92.81414)
  line L436 (141.605, 124.5997) -> (141.605, 129.60858)
  line L437 (184.4675, 102.3747) -> (184.4675, 107.38358)
  line L438 (99.2378, 138.87704) -> (98.425, 138.87704)
  line L439 (65.06464, 40.73906) -> (61.89218, 39.26078)
  line L440 (198.4375, 78.84414) -> (184.4675, 78.84414)
  line L441 (199.2503, 83.3247) -> (199.2503, 79.82458)
  line L442 (184.4675, 130.91414) -> (198.4375, 130.91414)
  line L443 (198.4375, 107.38358) -> (198.4375, 102.3747)
  line L444 (184.4675, 117.92458) -> (183.6547, 117.92458)
  line L445 (183.6547, 79.82458) -> (183.6547, 83.3247)
  line L446 (184.4675, 116.94414) -> (184.4675, 117.92458)
  line L447 (184.4675, 78.84414) -> (184.4675, 79.82458)
  line L448 (198.4375, 129.9337) -> (199.2503, 129.9337)
  line L449 (184.4675, 136.97204) -> (183.6547, 136.97204)
  line L450 (199.2503, 110.8837) -> (199.2503, 107.38358)
  line L451 (184.4675, 97.89414) -> (184.4675, 98.87458)
  line L452 (198.4375, 97.89414) -> (184.4675, 97.89414)
  line L453 (198.4375, 121.4247) -> (199.2503, 121.4247)
  line L454 (183.6547, 148.98116) -> (184.4675, 148.98116)
  line L455 (198.4375, 126.43358) -> (198.4375, 121.4247)
  line L456 (184.4675, 140.47216) -> (184.4675, 145.48104)
  line L457 (183.6547, 117.92458) -> (183.6547, 121.4247)
  line L458 (199.2503, 79.82458) -> (198.4375, 79.82458)
  line L459 (198.4375, 79.82458) -> (198.4375, 78.84414)
  line L460 (198.4375, 135.9916) -> (184.4675, 135.9916)
  line L461 (184.4675, 79.82458) -> (183.6547, 79.82458)
  line L462 (183.6547, 145.48104) -> (183.6547, 148.98116)
  line L463 (198.4375, 130.91414) -> (198.4375, 129.9337)
  line L464 (184.4675, 148.98116) -> (184.4675, 149.9616)
  line L465 (183.6547, 102.3747) -> (184.4675, 102.3747)
  line L466 (183.6547, 140.47216) -> (184.4675, 140.47216)
  line L467 (183.6547, 126.43358) -> (183.6547, 129.9337)
  line L468 (183.6547, 107.38358) -> (183.6547, 110.8837)
  line L469 (198.4375, 116.94414) -> (184.4675, 116.94414)
  line L470 (199.2503, 121.4247) -> (199.2503, 117.92458)
  line L471 (198.4375, 110.8837) -> (199.2503, 110.8837)
  line L472 (184.4675, 98.87458) -> (183.6547, 98.87458)
  line L473 (184.4675, 135.9916) -> (184.4675, 136.97204)
  line L474 (184.4675, 126.43358) -> (183.6547, 126.43358)
  line L475 (183.6547, 110.8837) -> (184.4675, 110.8837)
  line L476 (184.4675, 121.4247) -> (184.4675, 126.43358)
  line L477 (184.4675, 111.86414) -> (198.4375, 111.86414)
  line L478 (184.4675, 129.9337) -> (184.4675, 130.91414)
  line L479 (183.6547, 129.9337) -> (184.4675, 129.9337)
  line L480 (198.4375, 92.81414) -> (198.4375, 91.8337)
  line L481 (199.2503, 98.87458) -> (198.4375, 98.87458)
  line L482 (199.2503, 88.33358) -> (198.4375, 88.33358)
  line L483 (198.4375, 102.3747) -> (199.2503, 102.3747)
  line L484 (199.2503, 117.92458) -> (198.4375, 117.92458)
  line L485 (184.4675, 145.48104) -> (183.6547, 145.48104)
  line L486 (183.6547, 98.87458) -> (183.6547, 102.3747)
  line L487 (199.2503, 129.9337) -> (199.2503, 126.43358)
  line L488 (198.4375, 88.33358) -> (198.4375, 83.3247)
  line L489 (199.2503, 107.38358) -> (198.4375, 107.38358)
  line L490 (183.6547, 136.97204) -> (183.6547, 140.47216)
  line L491 (89.5, 181.50078) -> (89.5, 180)
  circle A0 centre (59.991271, 180.349827) radius 1.5
  line L492 (184.4675, 88.33358) -> (183.6547, 88.33358)
  line L493 (123.0122, 186.6138) -> (103.9368, 186.6138)
  line L494 (184.4675, 91.8337) -> (184.4675, 92.81414)
  line L495 (83.5, 180) -> (80, 180)
  line L496 (92.7708, 169.542814) -> (95.766352, 169.540887)
  arc A1 (16.26893, 78.802635) -> (12.882887, 69.500077) centre (19.227051, 72.458384) ccw
  line L497 (52.65674, 58.54954) -> (65.3161, 64.45504)
  line L498 (198.4375, 98.87458) -> (198.4375, 97.89414)
  line L499 (91.29014, 50.22342) -> (92.6846, 47.2313)
  line L500 (80.02524, 41.3258) -> (78.62824, 44.31792)
  line L501 (81.19872, 71.86168) -> (82.59572, 68.86956)
  line L502 (54.0512, 55.55742) -> (52.65674, 58.54954)
  line L503 (174.625, 145.48104) -> (174.625, 140.47216)
  line L504 (137.3378, 153.75636) -> (137.3378, 150.25624)
  line L505 (102.6922, 148.65858) -> (102.6922, 152.1587)
  line L506 (140.7922, 72.45858) -> (140.7922, 75.9587)
  line L507 (156.3878, 152.1587) -> (156.3878, 148.65858)
  line L508 (174.625, 126.43358) -> (174.625, 121.4247)
  line L509 (160.655, 129.9337) -> (160.655, 130.91414)
  line L510 (118.2878, 140.14958) -> (117.475, 140.14958)
  line L511 (122.555, 150.25624) -> (121.7422, 150.25624)
  line L512 (136.525, 131.20624) -> (136.525, 126.19736)
  line L513 (155.575, 62.96914) -> (141.605, 62.96914)
  line L514 (175.4378, 121.4247) -> (175.4378, 117.92458)
  line L515 (175.4378, 126.43358) -> (174.625, 126.43358)
  line L516 (156.3878, 72.45858) -> (155.575, 72.45858)
  line L517 (160.655, 116.94414) -> (160.655, 117.92458)